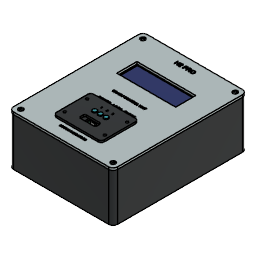
H2_Brain_LCD2004_v2 (Autodesk Fusion 360 design; units mm, degrees)
part number: 2026-09-27-10-19-20-342
part number: 2026-09-27-10-19-20-901
part number: 2026-09-27-10-19-24-013
part number: 2026-09-27-15-15-21-685
part number: 2026-09-27-15-15-23-118
part number: 2026-09-27-15-15-24-603
part number: 2026-09-27-15-15-26-161
part number: 2026-09-27-15-15-30-114
part number: 2026-09-27-15-15-31-956
part number: 2026-09-27-15-15-34-204
part number: 2026-09-27-15-15-36-656
part number: 2026-09-27-15-16-00-615
part number: 2026-09-27-15-16-12-198
part number: 2026-09-27-15-16-21-638
part number: 2026-09-27-15-16-25-058
part number: 2026-09-27-15-16-28-628
part number: 2026-09-27-15-16-32-419
part number: 2026-09-27-15-16-41-513
part number: 2026-09-27-15-16-51-300
part number: 2026-09-27-15-16-59-143
Autodesk Fusion 360 part; units mm, degrees
(part 1 of 2)
sketch "Outer shell sketch" plane through (0, 0, 0) normal (0, 0, 1) x (1, 0, 0) in component "01 BASE - PCB at bottom"
  line L0 (6, 0) -> (134, 0)
  line L1 (140, 6) -> (140, 154)
  line L2 (134, 160) -> (6, 160)
  line L3 (0, 154) -> (0, 6)
  arc A0 (134, 0) -> (140, 6) centre (134, 6) ccw
  arc A1 (140, 154) -> (134, 160) centre (134, 154) ccw
  arc A2 (6, 160) -> (0, 154) centre (6, 154) ccw
  arc A3 (0, 6) -> (6, 0) centre (6, 6) ccw
extrude "Outer shell" add sketch "Outer shell sketch" along normal blind 52 makes body 1 in component "01 BASE - PCB at bottom"
ref_plane "WorkPlane1" through (0, 0, 3) normal (0, 0, 1) x (1, 0, 0) in component "01 BASE - PCB at bottom"
sketch "Hollow cavity sketch" plane through (0, 0, 3) normal (0, 0, 1) x (1, 0, 0) in component "01 BASE - PCB at bottom"
  line L0 (6, 3) -> (134, 3)
  line L1 (137, 6) -> (137, 154)
  line L2 (134, 157) -> (6, 157)
  line L3 (3, 154) -> (3, 6)
  arc A0 (134, 3) -> (137, 6) centre (134, 6) ccw
  arc A1 (137, 154) -> (134, 157) centre (134, 154) ccw
  arc A2 (6, 157) -> (3, 154) centre (6, 154) ccw
  arc A3 (3, 6) -> (6, 3) centre (6, 6) ccw
extrude "Hollow cavity" cut sketch "Hollow cavity sketch" along normal blind 50 bodies 1 in component "01 BASE - PCB at bottom"
ref_plane "WorkPlane2" through (0, 0, 3) normal (0, 0, 1) x (1, 0, 0) in component "01 BASE - PCB at bottom"
sketch "Four lid screw pillars" plane through (0, 0, 3) normal (0, 0, 1) x (1, 0, 0) in component "01 BASE - PCB at bottom"
  line L0 (3, 3) -> (13, 3)
  line L1 (13, 3) -> (13, 13)
  line L2 (13, 13) -> (3, 13)
  line L3 (3, 13) -> (3, 3)
  line L4 (127, 3) -> (137, 3)
  line L5 (137, 3) -> (137, 13)
  line L6 (137, 13) -> (127, 13)
  line L7 (127, 13) -> (127, 3)
  line L8 (3, 147) -> (13, 147)
  line L9 (13, 147) -> (13, 157)
  line L10 (13, 157) -> (3, 157)
  line L11 (3, 157) -> (3, 147)
  line L12 (127, 147) -> (137, 147)
  line L13 (137, 147) -> (137, 157)
  line L14 (137, 157) -> (127, 157)
  line L15 (127, 157) -> (127, 147)
extrude "Lid pillars" add sketch "Four lid screw pillars" along normal blind 49 bodies 1 in component "01 BASE - PCB at bottom"
ref_plane "WorkPlane3" through (0, 0, 40) normal (0, 0, 1) x (1, 0, 0) in component "01 BASE - PCB at bottom"
sketch "M3 lid pilot holes sketch" plane through (0, 0, 40) normal (0, 0, 1) x (1, 0, 0) in component "01 BASE - PCB at bottom"
  circle A0 centre (8, 8) radius 1.25
  circle A1 centre (132, 8) radius 1.25
  circle A2 centre (8, 152) radius 1.25
  circle A3 centre (132, 152) radius 1.25
  dimension "d17" = 2.5
  dimension "d18" = 2.5
  dimension "d19" = 2.5
  dimension "d20" = 2.5
  measures "d17" diameter of A0
  measures "d18" diameter of A1
  measures "d19" diameter of A2
  measures "d20" diameter of A3
extrude "M3 lid pilot holes" cut sketch "M3 lid pilot holes sketch" along normal blind 12.1 bodies 1 in component "01 BASE - PCB at bottom"
ref_plane "WorkPlane4" through (0, 0, 3) normal (0, 0, 1) x (1, 0, 0) in component "01 BASE - PCB at bottom"
sketch "PCB support pads" plane through (0, 0, 3) normal (0, 0, 1) x (1, 0, 0) in component "01 BASE - PCB at bottom"
  line L0 (23, 40) -> (29, 40)
  line L1 (29, 40) -> (29, 50)
  line L2 (29, 50) -> (23, 50)
  line L3 (23, 50) -> (23, 40)
  line L4 (23, 110) -> (29, 110)
  line L5 (29, 110) -> (29, 120)
  line L6 (29, 120) -> (23, 120)
  line L7 (23, 120) -> (23, 110)
  line L8 (111, 40) -> (117, 40)
  line L9 (117, 40) -> (117, 50)
  line L10 (117, 50) -> (111, 50)
  line L11 (111, 50) -> (111, 40)
  line L12 (111, 110) -> (117, 110)
  line L13 (117, 110) -> (117, 120)
  line L14 (117, 120) -> (111, 120)
  line L15 (111, 120) -> (111, 110)
extrude "PCB supports z8" add sketch "PCB support pads" along normal blind 5 bodies 1 in component "01 BASE - PCB at bottom"
ref_plane "WorkPlane5" through (0, 0, 3) normal (0, 0, 1) x (1, 0, 0) in component "01 BASE - PCB at bottom"
sketch "PCB lateral guides" plane through (0, 0, 3) normal (0, 0, 1) x (1, 0, 0) in component "01 BASE - PCB at bottom"
  line L0 (22.2, 40) -> (24.6, 40)
  line L1 (24.6, 40) -> (24.6, 50)
  line L2 (24.6, 50) -> (22.2, 50)
  line L3 (22.2, 50) -> (22.2, 40)
  line L4 (22.2, 110) -> (24.6, 110)
  line L5 (24.6, 110) -> (24.6, 120)
  line L6 (24.6, 120) -> (22.2, 120)
  line L7 (22.2, 120) -> (22.2, 110)
  line L8 (115.4, 40) -> (117.8, 40)
  line L9 (117.8, 40) -> (117.8, 50)
  line L10 (117.8, 50) -> (115.4, 50)
  line L11 (115.4, 50) -> (115.4, 40)
  line L12 (115.4, 110) -> (117.8, 110)
  line L13 (117.8, 110) -> (117.8, 120)
  line L14 (117.8, 120) -> (115.4, 120)
  line L15 (115.4, 120) -> (115.4, 110)
  line L16 (55, 27.2) -> (85, 27.2)
  line L17 (85, 27.2) -> (85, 29.6)
  line L18 (85, 29.6) -> (55, 29.6)
  line L19 (55, 29.6) -> (55, 27.2)
  line L20 (55, 130.4) -> (85, 130.4)
  line L21 (85, 130.4) -> (85, 132.8)
  line L22 (85, 132.8) -> (55, 132.8)
  line L23 (55, 132.8) -> (55, 130.4)
extrude "Board edge guides clearance 0.4" add sketch "PCB lateral guides" along normal blind 6.6 bodies 1 in component "01 BASE - PCB at bottom"
ref_plane "WorkPlane6" through (0, 0, 3) normal (0, 0, 1) x (1, 0, 0) in component "01 BASE - PCB at bottom"
sketch "Clamp screw pedestals sketch" plane through (0, 0, 3) normal (0, 0, 1) x (1, 0, 0) in component "01 BASE - PCB at bottom"
  circle A0 centre (20, 45) radius 4
  circle A1 centre (120, 45) radius 4
  circle A2 centre (20, 115) radius 4
  circle A3 centre (120, 115) radius 4
extrude "Clamp screw pedestals" add sketch "Clamp screw pedestals sketch" along normal blind 6.6 bodies 1 in component "01 BASE - PCB at bottom"
ref_plane "WorkPlane7" through (0, 0, 3.1) normal (0, 0, 1) x (1, 0, 0) in component "01 BASE - PCB at bottom"
sketch "M3 clamp pilots sketch" plane through (0, 0, 3.1) normal (0, 0, 1) x (1, 0, 0) in component "01 BASE - PCB at bottom"
  circle A0 centre (20, 45) radius 1.25
  circle A1 centre (120, 45) radius 1.25
  circle A2 centre (20, 115) radius 1.25
  circle A3 centre (120, 115) radius 1.25
  dimension "d37" = 2.5
  dimension "d38" = 2.5
  dimension "d39" = 2.5
  dimension "d40" = 2.5
  measures "d37" diameter of A0
  measures "d38" diameter of A1
  measures "d39" diameter of A2
  measures "d40" diameter of A3
extrude "M3 clamp pilots" cut sketch "M3 clamp pilots sketch" along normal blind 6.6 bodies 1 in component "01 BASE - PCB at bottom"
ref_plane "WorkPlane1" through (0, 0, 52) normal (0, 0, 1) x (1, 0, 0) in component "02 LID - LCD buttons LEDs"
sketch "Lid plate sketch" plane through (0, 0, 52) normal (0, 0, 1) x (1, 0, 0) in component "02 LID - LCD buttons LEDs"
  line L0 (6, 0) -> (134, 0)
  line L1 (140, 6) -> (140, 154)
  line L2 (134, 160) -> (6, 160)
  line L3 (0, 154) -> (0, 6)
  arc A0 (134, 0) -> (140, 6) centre (134, 6) ccw
  arc A1 (140, 154) -> (134, 160) centre (134, 154) ccw
  arc A2 (6, 160) -> (0, 154) centre (6, 154) ccw
  arc A3 (0, 6) -> (6, 0) centre (6, 6) ccw
extrude "Lid plate" add sketch "Lid plate sketch" along normal blind 3 separate body makes body 2 in component "02 LID - LCD buttons LEDs"
ref_plane "WorkPlane2" through (0, 0, 48) normal (0, 0, 1) x (1, 0, 0) in component "02 LID - LCD buttons LEDs"
sketch "Locating lip segments - 0.3 clearance" plane through (0, 0, 48) normal (0, 0, 1) x (1, 0, 0) in component "02 LID - LCD buttons LEDs"
  line L0 (3.3, 16) -> (5.3, 16)
  line L1 (5.3, 16) -> (5.3, 144)
  line L2 (5.3, 144) -> (3.3, 144)
  line L3 (3.3, 144) -> (3.3, 16)
  line L4 (134.7, 16) -> (136.7, 16)
  line L5 (136.7, 16) -> (136.7, 144)
  line L6 (136.7, 144) -> (134.7, 144)
  line L7 (134.7, 144) -> (134.7, 16)
  line L8 (16, 3.3) -> (124, 3.3)
  line L9 (124, 3.3) -> (124, 5.3)
  line L10 (124, 5.3) -> (16, 5.3)
  line L11 (16, 5.3) -> (16, 3.3)
  line L12 (16, 154.7) -> (124, 154.7)
  line L13 (124, 154.7) -> (124, 156.7)
  line L14 (124, 156.7) -> (16, 156.7)
  line L15 (16, 156.7) -> (16, 154.7)
extrude "Locating lips" add sketch "Locating lip segments - 0.3 clearance" along normal blind 4 bodies 2 in component "02 LID - LCD buttons LEDs"
ref_plane "WorkPlane3" through (0, 0, 51.9) normal (0, 0, 1) x (1, 0, 0) in component "02 LID - LCD buttons LEDs"
sketch "M3 lid through holes sketch" plane through (0, 0, 51.9) normal (0, 0, 1) x (1, 0, 0) in component "02 LID - LCD buttons LEDs"
  circle A0 centre (8, 8) radius 1.7
  circle A1 centre (132, 8) radius 1.7
  circle A2 centre (8, 152) radius 1.7
  circle A3 centre (132, 152) radius 1.7
  dimension "d53" = 3.4
  dimension "d54" = 3.4
  dimension "d55" = 3.4
  dimension "d56" = 3.4
  measures "d53" diameter of A0
  measures "d54" diameter of A1
  measures "d55" diameter of A2
  measures "d56" diameter of A3
extrude "M3 lid through holes" cut sketch "M3 lid through holes sketch" along normal blind 3.2 bodies 2 in component "02 LID - LCD buttons LEDs"
ref_plane "WorkPlane4" through (0, 0, 53.8) normal (0, 0, 1) x (1, 0, 0) in component "02 LID - LCD buttons LEDs"
sketch "Screw head pockets sketch" plane through (0, 0, 53.8) normal (0, 0, 1) x (1, 0, 0) in component "02 LID - LCD buttons LEDs"
  circle A0 centre (8, 8) radius 3.2
  circle A1 centre (132, 8) radius 3.2
  circle A2 centre (8, 152) radius 3.2
  circle A3 centre (132, 152) radius 3.2
extrude "Screw head pockets" cut sketch "Screw head pockets sketch" along normal blind 1.3 bodies 2 in component "02 LID - LCD buttons LEDs"
ref_plane "WorkPlane5" through (0, 0, 51.9) normal (0, 0, 1) x (1, 0, 0) in component "02 LID - LCD buttons LEDs"
sketch "LCD viewing aperture sketch" plane through (0, 0, 51.9) normal (0, 0, 1) x (1, 0, 0) in component "02 LID - LCD buttons LEDs"
  line L0 (30.5, 99.5) -> (109.5, 99.5)
  line L1 (109.5, 99.5) -> (109.5, 126.5)
  line L2 (109.5, 126.5) -> (30.5, 126.5)
  line L3 (30.5, 126.5) -> (30.5, 99.5)
extrude "LCD viewing aperture" cut sketch "LCD viewing aperture sketch" along normal blind 3.2 bodies 2 in component "02 LID - LCD buttons LEDs"
ref_plane "WorkPlane6" through (0, 0, 42) normal (0, 0, 1) x (1, 0, 0) in component "02 LID - LCD buttons LEDs"
sketch "LCD underside spacers sketch" plane through (0, 0, 42) normal (0, 0, 1) x (1, 0, 0) in component "02 LID - LCD buttons LEDs"
  circle A0 centre (23.5, 85.5) radius 3.5
  circle A1 centre (116.5, 85.5) radius 3.5
  circle A2 centre (23.5, 140.5) radius 3.5
  circle A3 centre (116.5, 140.5) radius 3.5
extrude "LCD underside spacers" add sketch "LCD underside spacers sketch" along normal blind 10 bodies 2 in component "02 LID - LCD buttons LEDs"
ref_plane "WorkPlane7" through (0, 0, 41.9) normal (0, 0, 1) x (1, 0, 0) in component "02 LID - LCD buttons LEDs"
sketch "LCD M3 pilot holes sketch" plane through (0, 0, 41.9) normal (0, 0, 1) x (1, 0, 0) in component "02 LID - LCD buttons LEDs"
  circle A0 centre (23.5, 85.5) radius 1.25
  circle A1 centre (116.5, 85.5) radius 1.25
  circle A2 centre (23.5, 140.5) radius 1.25
  circle A3 centre (116.5, 140.5) radius 1.25
  dimension "d73" = 2.5
  dimension "d74" = 2.5
  dimension "d75" = 2.5
  dimension "d76" = 2.5
  measures "d73" diameter of A0
  measures "d74" diameter of A1
  measures "d75" diameter of A2
  measures "d76" diameter of A3
extrude "LCD M3 pilot holes" cut sketch "LCD M3 pilot holes sketch" along normal blind 8.1 bodies 2 in component "02 LID - LCD buttons LEDs"
ref_plane "WorkPlane8" through (0, 0, 51.9) normal (0, 0, 1) x (1, 0, 0) in component "02 LID - LCD buttons LEDs"
sketch "Three panel buttons sketch" plane through (0, 0, 51.9) normal (0, 0, 1) x (1, 0, 0) in component "02 LID - LCD buttons LEDs"
  circle A0 centre (36, 65) radius 6.1
  circle A1 centre (70, 65) radius 6.1
  circle A2 centre (104, 65) radius 6.1
  dimension "d81" = 12.2
  dimension "d82" = 12.2
  dimension "d83" = 12.2
  measures "d81" diameter of A0
  measures "d82" diameter of A1
  measures "d83" diameter of A2
extrude "Three panel buttons" cut sketch "Three panel buttons sketch" along normal blind 3.2 bodies 2 in component "02 LID - LCD buttons LEDs"
ref_plane "WorkPlane9" through (0, 0, 51.9) normal (0, 0, 1) x (1, 0, 0) in component "02 LID - LCD buttons LEDs"
sketch "Three indicator LEDs sketch" plane through (0, 0, 51.9) normal (0, 0, 1) x (1, 0, 0) in component "02 LID - LCD buttons LEDs"
  circle A0 centre (36, 26) radius 2.6
  circle A1 centre (70, 26) radius 2.6
  circle A2 centre (104, 26) radius 2.6
  dimension "d88" = 5.2
  dimension "d89" = 5.2
  dimension "d90" = 5.2
  measures "d88" diameter of A0
  measures "d89" diameter of A1
  measures "d90" diameter of A2
extrude "Three indicator LEDs" cut sketch "Three indicator LEDs sketch" along normal blind 3.2 bodies 2 in component "02 LID - LCD buttons LEDs"
ref_plane "WorkPlane10" through (0, 0, 55) normal (0, 0, 1) x (1, 0, 0) in component "02 LID - LCD buttons LEDs"
sketch "Engraving H2 PRO" plane through (0, 0, 55) normal (0, 0, 1) x (1, 0, 0) in component "02 LID - LCD buttons LEDs"
  line L0 (37.5, 144.5) -> (102.5, 144.5) construction
  line L1 (102.5, 144.5) -> (102.5, 149.5) construction
  line L2 (102.5, 149.5) -> (37.5, 149.5) construction
  line L3 (37.5, 149.5) -> (37.5, 144.5) construction
  dimension "d95" = 4
  dimension "d96" = 0
  text T0 "H2 PRO" font "Arial" height 4 align centre middle in box 65 x 5 at (37.5, 144.5) x (1, 0) y (0, 1) spacing 1 kerned
extrude "Engrave H2 PRO" cut sketch "Engraving H2 PRO" against normal blind 0.4 text T0 bodies 2 in component "02 LID - LCD buttons LEDs"
ref_plane "WorkPlane11" through (0, 0, 55) normal (0, 0, 1) x (1, 0, 0) in component "02 LID - LCD buttons LEDs"
sketch "Engraving POWER" plane through (0, 0, 55) normal (0, 0, 1) x (1, 0, 0) in component "02 LID - LCD buttons LEDs"
  line L0 (21, 48.5) -> (51, 48.5) construction
  line L1 (51, 48.5) -> (51, 53.5) construction
  line L2 (51, 53.5) -> (21, 53.5) construction
  line L3 (21, 53.5) -> (21, 48.5) construction
  dimension "d101" = 3
  text T0 "POWER" font "Arial" height 3 align centre middle in box 30 x 5 at (21, 48.5) x (1, 0) y (0, 1) spacing 1 kerned
extrude "Engrave POWER" cut sketch "Engraving POWER" against normal blind 0.4 text T0 bodies 2 in component "02 LID - LCD buttons LEDs"
ref_plane "WorkPlane12" through (0, 0, 55) normal (0, 0, 1) x (1, 0, 0) in component "02 LID - LCD buttons LEDs"
sketch "Engraving LOCK" plane through (0, 0, 55) normal (0, 0, 1) x (1, 0, 0) in component "02 LID - LCD buttons LEDs"
  line L0 (55, 48.5) -> (85, 48.5) construction
  line L1 (85, 48.5) -> (85, 53.5) construction
  line L2 (85, 53.5) -> (55, 53.5) construction
  line L3 (55, 53.5) -> (55, 48.5) construction
  dimension "d107" = 3
  text T0 "LOCK" font "Arial" height 3 align centre middle in box 30 x 5 at (55, 48.5) x (1, 0) y (0, 1) spacing 1 kerned
extrude "Engrave LOCK" cut sketch "Engraving LOCK" against normal blind 0.4 text T0 bodies 2 in component "02 LID - LCD buttons LEDs"
ref_plane "WorkPlane13" through (0, 0, 55) normal (0, 0, 1) x (1, 0, 0) in component "02 LID - LCD buttons LEDs"
sketch "Engraving PURGE" plane through (0, 0, 55) normal (0, 0, 1) x (1, 0, 0) in component "02 LID - LCD buttons LEDs"
  line L0 (89, 48.5) -> (119, 48.5) construction
  line L1 (119, 48.5) -> (119, 53.5) construction
  line L2 (119, 53.5) -> (89, 53.5) construction
  line L3 (89, 53.5) -> (89, 48.5) construction
  dimension "d113" = 3
  text T0 "PURGE" font "Arial" height 3 align centre middle in box 30 x 5 at (89, 48.5) x (1, 0) y (0, 1) spacing 1 kerned
extrude "Engrave PURGE" cut sketch "Engraving PURGE" against normal blind 0.4 text T0 bodies 2 in component "02 LID - LCD buttons LEDs"
ref_plane "WorkPlane14" through (0, 0, 55) normal (0, 0, 1) x (1, 0, 0) in component "02 LID - LCD buttons LEDs"
sketch "Engraving POWER (1)" plane through (0, 0, 55) normal (0, 0, 1) x (1, 0, 0) in component "02 LID - LCD buttons LEDs"
  line L0 (21, 13.5) -> (51, 13.5) construction
  line L1 (51, 13.5) -> (51, 18.5) construction
  line L2 (51, 18.5) -> (21, 18.5) construction
  line L3 (21, 18.5) -> (21, 13.5) construction
  dimension "d119" = 2.5
  text T0 "POWER" font "Arial" height 2.5 align centre middle in box 30 x 5 at (21, 13.5) x (1, 0) y (0, 1) spacing 1 kerned
extrude "Engrave POWER (1)" cut sketch "Engraving POWER (1)" against normal blind 0.4 text T0 bodies 2 in component "02 LID - LCD buttons LEDs"
ref_plane "WorkPlane15" through (0, 0, 55) normal (0, 0, 1) x (1, 0, 0) in component "02 LID - LCD buttons LEDs"
sketch "Engraving LOCK (1)" plane through (0, 0, 55) normal (0, 0, 1) x (1, 0, 0) in component "02 LID - LCD buttons LEDs"
  line L0 (55, 13.5) -> (85, 13.5) construction
  line L1 (85, 13.5) -> (85, 18.5) construction
  line L2 (85, 18.5) -> (55, 18.5) construction
  line L3 (55, 18.5) -> (55, 13.5) construction
  dimension "d125" = 2.5
  text T0 "LOCK" font "Arial" height 2.5 align centre middle in box 30 x 5 at (55, 13.5) x (1, 0) y (0, 1) spacing 1 kerned
extrude "Engrave LOCK (1)" cut sketch "Engraving LOCK (1)" against normal blind 0.4 text T0 bodies 2 in component "02 LID - LCD buttons LEDs"
ref_plane "WorkPlane16" through (0, 0, 55) normal (0, 0, 1) x (1, 0, 0) in component "02 LID - LCD buttons LEDs"
sketch "Engraving MODE" plane through (0, 0, 55) normal (0, 0, 1) x (1, 0, 0) in component "02 LID - LCD buttons LEDs"
  line L0 (89, 13.5) -> (119, 13.5) construction
  line L1 (119, 13.5) -> (119, 18.5) construction
  line L2 (119, 18.5) -> (89, 18.5) construction
  line L3 (89, 18.5) -> (89, 13.5) construction
  dimension "d131" = 2.5
  text T0 "MODE" font "Arial" height 2.5 align centre middle in box 30 x 5 at (89, 13.5) x (1, 0) y (0, 1) spacing 1 kerned
extrude "Engrave MODE" cut sketch "Engraving MODE" against normal blind 0.4 text T0 bodies 2 in component "02 LID - LCD buttons LEDs"
sketch "V2 extend existing base for relay bay sketch" plane through (0, 0, 0) normal (0, 0, 1) x (1, 0, 0) in component "01 BASE - PCB at bottom"
  line L0 (6, 0) -> (134, 0)
  line L1 (140, 6) -> (140, 174)
  line L2 (134, 180) -> (6, 180)
  line L3 (0, 174) -> (0, 6)
  arc A0 (134, 0) -> (140, 6) centre (134, 6) ccw
  arc A1 (140, 174) -> (134, 180) centre (134, 174) ccw
  arc A2 (6, 180) -> (0, 174) centre (6, 174) ccw
  arc A3 (0, 6) -> (6, 0) centre (6, 6) ccw
extrude "V2 extend existing base for relay bay" add sketch "V2 extend existing base for relay bay sketch" along normal blind 64 bodies 1 in component "01 BASE - PCB at bottom"
ref_plane "WorkPlane8" through (0, 0, 3) normal (0, 0, 1) x (1, 0, 0) in component "01 BASE - PCB at bottom"
sketch "V2 clear obsolete interior mounts sketch" plane through (0, 0, 3) normal (0, 0, 1) x (1, 0, 0) in component "01 BASE - PCB at bottom"
  line L0 (6, 3) -> (134, 3)
  line L1 (137, 6) -> (137, 174)
  line L2 (134, 177) -> (6, 177)
  line L3 (3, 174) -> (3, 6)
  arc A0 (134, 3) -> (137, 6) centre (134, 6) ccw
  arc A1 (137, 174) -> (134, 177) centre (134, 174) ccw
  arc A2 (6, 177) -> (3, 174) centre (6, 174) ccw
  arc A3 (3, 6) -> (6, 3) centre (6, 6) ccw
extrude "V2 clear obsolete interior mounts" cut sketch "V2 clear obsolete interior mounts sketch" along normal blind 62 bodies 1 in component "01 BASE - PCB at bottom"
ref_plane "WorkPlane9" through (0, 0, 3) normal (0, 0, 1) x (1, 0, 0) in component "01 BASE - PCB at bottom"
sketch "V2 lid pillars" plane through (0, 0, 3) normal (0, 0, 1) x (1, 0, 0) in component "01 BASE - PCB at bottom"
  line L0 (3, 3) -> (13, 3)
  line L1 (13, 3) -> (13, 13)
  line L2 (13, 13) -> (3, 13)
  line L3 (3, 13) -> (3, 3)
  line L4 (127, 3) -> (137, 3)
  line L5 (137, 3) -> (137, 13)
  line L6 (137, 13) -> (127, 13)
  line L7 (127, 13) -> (127, 3)
  line L8 (3, 167) -> (13, 167)
  line L9 (13, 167) -> (13, 177)
  line L10 (13, 177) -> (3, 177)
  line L11 (3, 177) -> (3, 167)
  line L12 (127, 167) -> (137, 167)
  line L13 (137, 167) -> (137, 177)
  line L14 (137, 177) -> (127, 177)
  line L15 (127, 177) -> (127, 167)
extrude "V2 four cover pillars" add sketch "V2 lid pillars" along normal blind 61 bodies 1 in component "01 BASE - PCB at bottom"
ref_plane "WorkPlane10" through (0, 0, 52) normal (0, 0, 1) x (1, 0, 0) in component "01 BASE - PCB at bottom"
sketch "V2 lid pilots sketch" plane through (0, 0, 52) normal (0, 0, 1) x (1, 0, 0) in component "01 BASE - PCB at bottom"
  circle A0 centre (8, 8) radius 1.25
  circle A1 centre (132, 8) radius 1.25
  circle A2 centre (8, 172) radius 1.25
  circle A3 centre (132, 172) radius 1.25
extrude "V2 lid pilots" cut sketch "V2 lid pilots sketch" along normal blind 12.2 bodies 1 in component "01 BASE - PCB at bottom"
ref_plane "WorkPlane11" through (0, 0, 3) normal (0, 0, 1) x (1, 0, 0) in component "01 BASE - PCB at bottom"
sketch "V2 MAIN supports" plane through (0, 0, 3) normal (0, 0, 1) x (1, 0, 0) in component "01 BASE - PCB at bottom"
  line L0 (23, 30) -> (29, 30)
  line L1 (29, 30) -> (29, 40)
  line L2 (29, 40) -> (23, 40)
  line L3 (23, 40) -> (23, 30)
  line L4 (23, 80) -> (29, 80)
  line L5 (29, 80) -> (29, 90)
  line L6 (29, 90) -> (23, 90)
  line L7 (23, 90) -> (23, 80)
  line L8 (111, 30) -> (117, 30)
  line L9 (117, 30) -> (117, 40)
  line L10 (117, 40) -> (111, 40)
  line L11 (111, 40) -> (111, 30)
  line L12 (111, 80) -> (117, 80)
  line L13 (117, 80) -> (117, 90)
  line L14 (117, 90) -> (111, 90)
  line L15 (111, 90) -> (111, 80)
extrude "V2 MAIN underside edge pads" add sketch "V2 MAIN supports" along normal blind 5 bodies 1 in component "01 BASE - PCB at bottom"
ref_plane "WorkPlane12" through (0, 0, 3) normal (0, 0, 1) x (1, 0, 0) in component "01 BASE - PCB at bottom"
sketch "V2 MAIN clamp pedestals sketch" plane through (0, 0, 3) normal (0, 0, 1) x (1, 0, 0) in component "01 BASE - PCB at bottom"
  circle A0 centre (20, 35) radius 4
  circle A1 centre (120, 35) radius 4
  circle A2 centre (20, 85) radius 4
  circle A3 centre (120, 85) radius 4
extrude "V2 MAIN clamp pedestals" add sketch "V2 MAIN clamp pedestals sketch" along normal blind 6.6 bodies 1 in component "01 BASE - PCB at bottom"
ref_plane "WorkPlane13" through (0, 0, 3.1) normal (0, 0, 1) x (1, 0, 0) in component "01 BASE - PCB at bottom"
sketch "V2 MAIN clamp pilots sketch" plane through (0, 0, 3.1) normal (0, 0, 1) x (1, 0, 0) in component "01 BASE - PCB at bottom"
  circle A0 centre (20, 35) radius 1.25
  circle A1 centre (120, 35) radius 1.25
  circle A2 centre (20, 85) radius 1.25
  circle A3 centre (120, 85) radius 1.25
extrude "V2 MAIN clamp pilots" cut sketch "V2 MAIN clamp pilots sketch" along normal blind 6.6 bodies 1 in component "01 BASE - PCB at bottom"
ref_plane "WorkPlane1" through (0, 0, 9.6) normal (0, 0, 1) x (1, 0, 0) in component "V2 MAIN clamp 1"
sketch "Edge clamp sketch" plane through (0, 0, 9.6) normal (0, 0, 1) x (1, 0, 0) in component "V2 MAIN clamp 1"
  line L0 (17, 30) -> (27.5, 30)
  line L1 (28.5, 31) -> (28.5, 39)
  line L2 (27.5, 40) -> (17, 40)
  line L3 (16, 39) -> (16, 31)
  arc A0 (27.5, 30) -> (28.5, 31) centre (27.5, 31) ccw
  arc A1 (28.5, 39) -> (27.5, 40) centre (27.5, 39) ccw
  arc A2 (17, 40) -> (16, 39) centre (17, 39) ccw
  arc A3 (16, 31) -> (17, 30) centre (17, 31) ccw
extrude "Edge clamp" add sketch "Edge clamp sketch" along normal blind 2.5 separate body makes body 3 in component "V2 MAIN clamp 1"
ref_plane "WorkPlane2" through (0, 0, 9.5) normal (0, 0, 1) x (1, 0, 0) in component "V2 MAIN clamp 1"
sketch "Clamp adjustment slot" plane through (0, 0, 9.5) normal (0, 0, 1) x (1, 0, 0) in component "V2 MAIN clamp 1"
  line L0 (18.4, 33.3) -> (21.6, 33.3)
  line L1 (23.2, 34.9) -> (23.2, 35.1)
  line L2 (21.6, 36.7) -> (18.4, 36.7)
  line L3 (16.8, 35.1) -> (16.8, 34.9)
  arc A0 (21.6, 33.3) -> (23.2, 34.9) centre (21.6, 34.9) ccw
  arc A1 (23.2, 35.1) -> (21.6, 36.7) centre (21.6, 35.1) ccw
  arc A2 (18.4, 36.7) -> (16.8, 35.1) centre (18.4, 35.1) ccw
  arc A3 (16.8, 34.9) -> (18.4, 33.3) centre (18.4, 34.9) ccw
extrude "Clamp adjustment slot (1)" cut sketch "Clamp adjustment slot" along normal blind 2.8 bodies 3 in component "V2 MAIN clamp 1"
ref_plane "WorkPlane1" through (0, 0, 9.6) normal (0, 0, 1) x (1, 0, 0) in component "V2 MAIN clamp 2"
sketch "Edge clamp sketch (2)" plane through (0, 0, 9.6) normal (0, 0, 1) x (1, 0, 0) in component "V2 MAIN clamp 2"
  line L0 (112.5, 30) -> (123, 30)
  line L1 (124, 31) -> (124, 39)
  line L2 (123, 40) -> (112.5, 40)
  line L3 (111.5, 39) -> (111.5, 31)
  arc A0 (123, 30) -> (124, 31) centre (123, 31) ccw
  arc A1 (124, 39) -> (123, 40) centre (123, 39) ccw
  arc A2 (112.5, 40) -> (111.5, 39) centre (112.5, 39) ccw
  arc A3 (111.5, 31) -> (112.5, 30) centre (112.5, 31) ccw
extrude "Edge clamp'" add sketch "Edge clamp sketch (2)" along normal blind 2.5 separate body makes body 4 in component "V2 MAIN clamp 2"
ref_plane "WorkPlane2" through (0, 0, 9.5) normal (0, 0, 1) x (1, 0, 0) in component "V2 MAIN clamp 2"
sketch "Clamp adjustment slot (2)" plane through (0, 0, 9.5) normal (0, 0, 1) x (1, 0, 0) in component "V2 MAIN clamp 2"
  line L0 (118.4, 33.3) -> (121.6, 33.3)
  line L1 (123.2, 34.9) -> (123.2, 35.1)
  line L2 (121.6, 36.7) -> (118.4, 36.7)
  line L3 (116.8, 35.1) -> (116.8, 34.9)
  arc A0 (121.6, 33.3) -> (123.2, 34.9) centre (121.6, 34.9) ccw
  arc A1 (123.2, 35.1) -> (121.6, 36.7) centre (121.6, 35.1) ccw
  arc A2 (118.4, 36.7) -> (116.8, 35.1) centre (118.4, 35.1) ccw
  arc A3 (116.8, 34.9) -> (118.4, 33.3) centre (118.4, 34.9) ccw
extrude "Clamp adjustment slot (1)'" cut sketch "Clamp adjustment slot (2)" along normal blind 2.8 bodies 4 in component "V2 MAIN clamp 2"
ref_plane "WorkPlane1" through (0, 0, 9.6) normal (0, 0, 1) x (1, 0, 0) in component "V2 MAIN clamp 3"
sketch "Edge clamp sketch (3)" plane through (0, 0, 9.6) normal (0, 0, 1) x (1, 0, 0) in component "V2 MAIN clamp 3"
  line L0 (17, 80) -> (27.5, 80)
  line L1 (28.5, 81) -> (28.5, 89)
  line L2 (27.5, 90) -> (17, 90)
  line L3 (16, 89) -> (16, 81)
  arc A0 (27.5, 80) -> (28.5, 81) centre (27.5, 81) ccw
  arc A1 (28.5, 89) -> (27.5, 90) centre (27.5, 89) ccw
  arc A2 (17, 90) -> (16, 89) centre (17, 89) ccw
  arc A3 (16, 81) -> (17, 80) centre (17, 81) ccw
extrude "Edge clamp''" add sketch "Edge clamp sketch (3)" along normal blind 2.5 separate body makes body 5 in component "V2 MAIN clamp 3"
ref_plane "WorkPlane2" through (0, 0, 9.5) normal (0, 0, 1) x (1, 0, 0) in component "V2 MAIN clamp 3"
sketch "Clamp adjustment slot (3)" plane through (0, 0, 9.5) normal (0, 0, 1) x (1, 0, 0) in component "V2 MAIN clamp 3"
  line L0 (18.4, 83.3) -> (21.6, 83.3)
  line L1 (23.2, 84.9) -> (23.2, 85.1)
  line L2 (21.6, 86.7) -> (18.4, 86.7)
  line L3 (16.8, 85.1) -> (16.8, 84.9)
  arc A0 (21.6, 83.3) -> (23.2, 84.9) centre (21.6, 84.9) ccw
  arc A1 (23.2, 85.1) -> (21.6, 86.7) centre (21.6, 85.1) ccw
  arc A2 (18.4, 86.7) -> (16.8, 85.1) centre (18.4, 85.1) ccw
  arc A3 (16.8, 84.9) -> (18.4, 83.3) centre (18.4, 84.9) ccw
extrude "Clamp adjustment slot (1)''" cut sketch "Clamp adjustment slot (3)" along normal blind 2.8 bodies 5 in component "V2 MAIN clamp 3"
ref_plane "WorkPlane1" through (0, 0, 9.6) normal (0, 0, 1) x (1, 0, 0) in component "V2 MAIN clamp 4"
sketch "Edge clamp sketch (4)" plane through (0, 0, 9.6) normal (0, 0, 1) x (1, 0, 0) in component "V2 MAIN clamp 4"
  line L0 (112.5, 80) -> (123, 80)
  line L1 (124, 81) -> (124, 89)
  line L2 (123, 90) -> (112.5, 90)
  line L3 (111.5, 89) -> (111.5, 81)
  arc A0 (123, 80) -> (124, 81) centre (123, 81) ccw
  arc A1 (124, 89) -> (123, 90) centre (123, 89) ccw
  arc A2 (112.5, 90) -> (111.5, 89) centre (112.5, 89) ccw
  arc A3 (111.5, 81) -> (112.5, 80) centre (112.5, 81) ccw
extrude "Edge clamp'''" add sketch "Edge clamp sketch (4)" along normal blind 2.5 separate body makes body 6 in component "V2 MAIN clamp 4"
ref_plane "WorkPlane2" through (0, 0, 9.5) normal (0, 0, 1) x (1, 0, 0) in component "V2 MAIN clamp 4"
sketch "Clamp adjustment slot (4)" plane through (0, 0, 9.5) normal (0, 0, 1) x (1, 0, 0) in component "V2 MAIN clamp 4"
  line L0 (118.4, 83.3) -> (121.6, 83.3)
  line L1 (123.2, 84.9) -> (123.2, 85.1)
  line L2 (121.6, 86.7) -> (118.4, 86.7)
  line L3 (116.8, 85.1) -> (116.8, 84.9)
  arc A0 (121.6, 83.3) -> (123.2, 84.9) centre (121.6, 84.9) ccw
  arc A1 (123.2, 85.1) -> (121.6, 86.7) centre (121.6, 85.1) ccw
  arc A2 (118.4, 86.7) -> (116.8, 85.1) centre (118.4, 85.1) ccw
  arc A3 (116.8, 84.9) -> (118.4, 83.3) centre (118.4, 84.9) ccw
extrude "Clamp adjustment slot (1)'''" cut sketch "Clamp adjustment slot (4)" along normal blind 2.8 bodies 6 in component "V2 MAIN clamp 4"
ref_plane "WorkPlane14" through (0, 0, 3) normal (0, 0, 1) x (1, 0, 0) in component "01 BASE - PCB at bottom"
sketch "V2 RELAY supports" plane through (0, 0, 3) normal (0, 0, 1) x (1, 0, 0) in component "01 BASE - PCB at bottom"
  line L0 (33, 122) -> (39, 122)
  line L1 (39, 122) -> (39, 132)
  line L2 (39, 132) -> (33, 132)
  line L3 (33, 132) -> (33, 122)
  line L4 (33, 152) -> (39, 152)
  line L5 (39, 152) -> (39, 162)
  line L6 (39, 162) -> (33, 162)
  line L7 (33, 162) -> (33, 152)
  line L8 (101, 122) -> (107, 122)
  line L9 (107, 122) -> (107, 132)
  line L10 (107, 132) -> (101, 132)
  line L11 (101, 132) -> (101, 122)
  line L12 (101, 152) -> (107, 152)
  line L13 (107, 152) -> (107, 162)
  line L14 (107, 162) -> (101, 162)
  line L15 (101, 162) -> (101, 152)
extrude "V2 RELAY underside edge pads" add sketch "V2 RELAY supports" along normal blind 5 bodies 1 in component "01 BASE - PCB at bottom"
ref_plane "WorkPlane15" through (0, 0, 3) normal (0, 0, 1) x (1, 0, 0) in component "01 BASE - PCB at bottom"
sketch "V2 RELAY clamp pedestals sketch" plane through (0, 0, 3) normal (0, 0, 1) x (1, 0, 0) in component "01 BASE - PCB at bottom"
  circle A0 centre (30, 127) radius 4
  circle A1 centre (110, 127) radius 4
  circle A2 centre (30, 157) radius 4
  circle A3 centre (110, 157) radius 4
extrude "V2 RELAY clamp pedestals" add sketch "V2 RELAY clamp pedestals sketch" along normal blind 6.6 bodies 1 in component "01 BASE - PCB at bottom"
ref_plane "WorkPlane16" through (0, 0, 3.1) normal (0, 0, 1) x (1, 0, 0) in component "01 BASE - PCB at bottom"
sketch "V2 RELAY clamp pilots sketch" plane through (0, 0, 3.1) normal (0, 0, 1) x (1, 0, 0) in component "01 BASE - PCB at bottom"
  circle A0 centre (30, 127) radius 1.25
  circle A1 centre (110, 127) radius 1.25
  circle A2 centre (30, 157) radius 1.25
  circle A3 centre (110, 157) radius 1.25
extrude "V2 RELAY clamp pilots" cut sketch "V2 RELAY clamp pilots sketch" along normal blind 6.6 bodies 1 in component "01 BASE - PCB at bottom"
ref_plane "WorkPlane1" through (0, 0, 9.6) normal (0, 0, 1) x (1, 0, 0) in component "V2 RELAY clamp 1"
sketch "Edge clamp sketch (5)" plane through (0, 0, 9.6) normal (0, 0, 1) x (1, 0, 0) in component "V2 RELAY clamp 1"
  line L0 (27, 122) -> (37.5, 122)
  line L1 (38.5, 123) -> (38.5, 131)
  line L2 (37.5, 132) -> (27, 132)
  line L3 (26, 131) -> (26, 123)
  arc A0 (37.5, 122) -> (38.5, 123) centre (37.5, 123) ccw
  arc A1 (38.5, 131) -> (37.5, 132) centre (37.5, 131) ccw
  arc A2 (27, 132) -> (26, 131) centre (27, 131) ccw
  arc A3 (26, 123) -> (27, 122) centre (27, 123) ccw
extrude "Edge clamp''''" add sketch "Edge clamp sketch (5)" along normal blind 2.5 separate body makes body 7 in component "V2 RELAY clamp 1"
ref_plane "WorkPlane2" through (0, 0, 9.5) normal (0, 0, 1) x (1, 0, 0) in component "V2 RELAY clamp 1"
sketch "Clamp adjustment slot (5)" plane through (0, 0, 9.5) normal (0, 0, 1) x (1, 0, 0) in component "V2 RELAY clamp 1"
  line L0 (28.4, 125.3) -> (31.6, 125.3)
  line L1 (33.2, 126.9) -> (33.2, 127.1)
  line L2 (31.6, 128.7) -> (28.4, 128.7)
  line L3 (26.8, 127.1) -> (26.8, 126.9)
  arc A0 (31.6, 125.3) -> (33.2, 126.9) centre (31.6, 126.9) ccw
  arc A1 (33.2, 127.1) -> (31.6, 128.7) centre (31.6, 127.1) ccw
  arc A2 (28.4, 128.7) -> (26.8, 127.1) centre (28.4, 127.1) ccw
  arc A3 (26.8, 126.9) -> (28.4, 125.3) centre (28.4, 126.9) ccw
extrude "Clamp adjustment slot (1)''''" cut sketch "Clamp adjustment slot (5)" along normal blind 2.8 bodies 7 in component "V2 RELAY clamp 1"
ref_plane "WorkPlane1" through (0, 0, 9.6) normal (0, 0, 1) x (1, 0, 0) in component "V2 RELAY clamp 2"
sketch "Edge clamp sketch (6)" plane through (0, 0, 9.6) normal (0, 0, 1) x (1, 0, 0) in component "V2 RELAY clamp 2"
  line L0 (102.5, 122) -> (113, 122)
  line L1 (114, 123) -> (114, 131)
  line L2 (113, 132) -> (102.5, 132)
  line L3 (101.5, 131) -> (101.5, 123)
  arc A0 (113, 122) -> (114, 123) centre (113, 123) ccw
  arc A1 (114, 131) -> (113, 132) centre (113, 131) ccw
  arc A2 (102.5, 132) -> (101.5, 131) centre (102.5, 131) ccw
  arc A3 (101.5, 123) -> (102.5, 122) centre (102.5, 123) ccw
extrude "Edge clamp'''''" add sketch "Edge clamp sketch (6)" along normal blind 2.5 separate body makes body 8 in component "V2 RELAY clamp 2"
ref_plane "WorkPlane2" through (0, 0, 9.5) normal (0, 0, 1) x (1, 0, 0) in component "V2 RELAY clamp 2"
sketch "Clamp adjustment slot (6)" plane through (0, 0, 9.5) normal (0, 0, 1) x (1, 0, 0) in component "V2 RELAY clamp 2"
  line L0 (108.4, 125.3) -> (111.6, 125.3)
  line L1 (113.2, 126.9) -> (113.2, 127.1)
  line L2 (111.6, 128.7) -> (108.4, 128.7)
  line L3 (106.8, 127.1) -> (106.8, 126.9)
  arc A0 (111.6, 125.3) -> (113.2, 126.9) centre (111.6, 126.9) ccw
  arc A1 (113.2, 127.1) -> (111.6, 128.7) centre (111.6, 127.1) ccw
  arc A2 (108.4, 128.7) -> (106.8, 127.1) centre (108.4, 127.1) ccw
  arc A3 (106.8, 126.9) -> (108.4, 125.3) centre (108.4, 126.9) ccw
extrude "Clamp adjustment slot (1)'''''" cut sketch "Clamp adjustment slot (6)" along normal blind 2.8 bodies 8 in component "V2 RELAY clamp 2"
ref_plane "WorkPlane1" through (0, 0, 9.6) normal (0, 0, 1) x (1, 0, 0) in component "V2 RELAY clamp 3"
sketch "Edge clamp sketch (7)" plane through (0, 0, 9.6) normal (0, 0, 1) x (1, 0, 0) in component "V2 RELAY clamp 3"
  line L0 (27, 152) -> (37.5, 152)
  line L1 (38.5, 153) -> (38.5, 161)
  line L2 (37.5, 162) -> (27, 162)
  line L3 (26, 161) -> (26, 153)
  arc A0 (37.5, 152) -> (38.5, 153) centre (37.5, 153) ccw
  arc A1 (38.5, 161) -> (37.5, 162) centre (37.5, 161) ccw
  arc A2 (27, 162) -> (26, 161) centre (27, 161) ccw
  arc A3 (26, 153) -> (27, 152) centre (27, 153) ccw
extrude "Edge clamp''''''" add sketch "Edge clamp sketch (7)" along normal blind 2.5 separate body makes body 9 in component "V2 RELAY clamp 3"
ref_plane "WorkPlane2" through (0, 0, 9.5) normal (0, 0, 1) x (1, 0, 0) in component "V2 RELAY clamp 3"
sketch "Clamp adjustment slot (7)" plane through (0, 0, 9.5) normal (0, 0, 1) x (1, 0, 0) in component "V2 RELAY clamp 3"
  line L0 (28.4, 155.3) -> (31.6, 155.3)
  line L1 (33.2, 156.9) -> (33.2, 157.1)
  line L2 (31.6, 158.7) -> (28.4, 158.7)
  line L3 (26.8, 157.1) -> (26.8, 156.9)
  arc A0 (31.6, 155.3) -> (33.2, 156.9) centre (31.6, 156.9) ccw
  arc A1 (33.2, 157.1) -> (31.6, 158.7) centre (31.6, 157.1) ccw
  arc A2 (28.4, 158.7) -> (26.8, 157.1) centre (28.4, 157.1) ccw
  arc A3 (26.8, 156.9) -> (28.4, 155.3) centre (28.4, 156.9) ccw
extrude "Clamp adjustment slot (1)''''''" cut sketch "Clamp adjustment slot (7)" along normal blind 2.8 bodies 9 in component "V2 RELAY clamp 3"
ref_plane "WorkPlane1" through (0, 0, 9.6) normal (0, 0, 1) x (1, 0, 0) in component "V2 RELAY clamp 4"
sketch "Edge clamp sketch (8)" plane through (0, 0, 9.6) normal (0, 0, 1) x (1, 0, 0) in component "V2 RELAY clamp 4"
  line L0 (102.5, 152) -> (113, 152)
  line L1 (114, 153) -> (114, 161)
  line L2 (113, 162) -> (102.5, 162)
  line L3 (101.5, 161) -> (101.5, 153)
  arc A0 (113, 152) -> (114, 153) centre (113, 153) ccw
  arc A1 (114, 161) -> (113, 162) centre (113, 161) ccw
  arc A2 (102.5, 162) -> (101.5, 161) centre (102.5, 161) ccw
  arc A3 (101.5, 153) -> (102.5, 152) centre (102.5, 153) ccw
extrude "Edge clamp'''''''" add sketch "Edge clamp sketch (8)" along normal blind 2.5 separate body makes body 10 in component "V2 RELAY clamp 4"
ref_plane "WorkPlane2" through (0, 0, 9.5) normal (0, 0, 1) x (1, 0, 0) in component "V2 RELAY clamp 4"
sketch "Clamp adjustment slot (8)" plane through (0, 0, 9.5) normal (0, 0, 1) x (1, 0, 0) in component "V2 RELAY clamp 4"
  line L0 (108.4, 155.3) -> (111.6, 155.3)
  line L1 (113.2, 156.9) -> (113.2, 157.1)
  line L2 (111.6, 158.7) -> (108.4, 158.7)
  line L3 (106.8, 157.1) -> (106.8, 156.9)
  arc A0 (111.6, 155.3) -> (113.2, 156.9) centre (111.6, 156.9) ccw
  arc A1 (113.2, 157.1) -> (111.6, 158.7) centre (111.6, 157.1) ccw
  arc A2 (108.4, 158.7) -> (106.8, 157.1) centre (108.4, 157.1) ccw
  arc A3 (106.8, 156.9) -> (108.4, 155.3) centre (108.4, 156.9) ccw
extrude "Clamp adjustment slot (1)'''''''" cut sketch "Clamp adjustment slot (8)" along normal blind 2.8 bodies 10 in component "V2 RELAY clamp 4"
ref_plane "WorkPlane17" through (0, -176.5, 0) normal (0, 1, 0) x (0, 0, 1) in component "01 BASE - PCB at bottom"
sketch "V2 rear wiring outlet" plane through (0, -176.5, 0) normal (0, 1, 0) x (1, 0, 0) in component "01 BASE - PCB at bottom"
  line L0 (40, 14) -> (60, 14)
  line L1 (62, 16) -> (62, 22)
  line L2 (60, 24) -> (40, 24)
  line L3 (38, 22) -> (38, 16)
  arc A0 (60, 14) -> (62, 16) centre (60, 16) ccw
  arc A1 (62, 22) -> (60, 24) centre (60, 22) ccw
  arc A2 (40, 24) -> (38, 22) centre (40, 22) ccw
  arc A3 (38, 16) -> (40, 14) centre (40, 16) ccw
ref_plane "WorkPlane18" through (0, -176.5, 0) normal (0, 1, 0) x (0, 0, 1) in component "01 BASE - PCB at bottom"
sketch "V2 rear wiring outlet (1)" plane through (0, -176.5, 0) normal (0, 1, 0) x (1, 0, 0) in component "01 BASE - PCB at bottom"
  line L0 (80, 14) -> (100, 14)
  line L1 (102, 16) -> (102, 22)
  line L2 (100, 24) -> (80, 24)
  line L3 (78, 22) -> (78, 16)
  arc A0 (100, 14) -> (102, 16) centre (100, 16) ccw
  arc A1 (102, 22) -> (100, 24) centre (100, 22) ccw
  arc A2 (80, 24) -> (78, 22) centre (80, 22) ccw
  arc A3 (78, 16) -> (80, 14) centre (80, 16) ccw
ref_plane "WorkPlane19" through (0, 0, 3) normal (0, 0, 1) x (1, 0, 0) in component "01 BASE - PCB at bottom"
sketch "V2 cable tie anchor sketch" plane through (0, 0, 3) normal (0, 0, 1) x (1, 0, 0) in component "01 BASE - PCB at bottom"
  line L0 (37, 169) -> (44, 169)
  line L1 (44, 169) -> (44, 174)
  line L2 (44, 174) -> (37, 174)
  line L3 (37, 174) -> (37, 169)
extrude "V2 cable tie anchor" add sketch "V2 cable tie anchor sketch" along normal blind 8 bodies 1 in component "01 BASE - PCB at bottom"
ref_plane "WorkPlane20" through (0, 0, 5) normal (0, 0, 1) x (1, 0, 0) in component "01 BASE - PCB at bottom"
sketch "V2 cable tie tunnel sketch" plane through (0, 0, 5) normal (0, 0, 1) x (1, 0, 0) in component "01 BASE - PCB at bottom"
  line L0 (38.5, 168.9) -> (42.5, 168.9)
  line L1 (42.5, 168.9) -> (42.5, 174.1)
  line L2 (42.5, 174.1) -> (38.5, 174.1)
  line L3 (38.5, 174.1) -> (38.5, 168.9)
extrude "V2 cable tie tunnel" cut sketch "V2 cable tie tunnel sketch" along normal blind 3 bodies 1 in component "01 BASE - PCB at bottom"
ref_plane "WorkPlane21" through (0, 0, 3) normal (0, 0, 1) x (1, 0, 0) in component "01 BASE - PCB at bottom"
sketch "V2 cable tie anchor sketch (1)" plane through (0, 0, 3) normal (0, 0, 1) x (1, 0, 0) in component "01 BASE - PCB at bottom"
  line L0 (99, 169) -> (106, 169)
  line L1 (106, 169) -> (106, 174)
  line L2 (106, 174) -> (99, 174)
  line L3 (99, 174) -> (99, 169)
extrude "V2 cable tie anchor (1)" add sketch "V2 cable tie anchor sketch (1)" along normal blind 8 bodies 1 in component "01 BASE - PCB at bottom"
ref_plane "WorkPlane22" through (0, 0, 5) normal (0, 0, 1) x (1, 0, 0) in component "01 BASE - PCB at bottom"
sketch "V2 cable tie tunnel sketch (1)" plane through (0, 0, 5) normal (0, 0, 1) x (1, 0, 0) in component "01 BASE - PCB at bottom"
  line L0 (100.5, 168.9) -> (104.5, 168.9)
  line L1 (104.5, 168.9) -> (104.5, 174.1)
  line L2 (104.5, 174.1) -> (100.5, 174.1)
  line L3 (100.5, 174.1) -> (100.5, 168.9)
extrude "V2 cable tie tunnel (1)" cut sketch "V2 cable tie tunnel sketch (1)" along normal blind 3 bodies 1 in component "01 BASE - PCB at bottom"
ref_plane "WorkPlane17" through (0, 0, 52) normal (0, 0, 1) x (1, 0, 0) in component "02 LID - LCD buttons LEDs"
sketch "V2 refill old lid and extend sketch" plane through (0, 0, 52) normal (0, 0, 1) x (1, 0, 0) in component "02 LID - LCD buttons LEDs"
  line L0 (6, 0) -> (134, 0)
  line L1 (140, 6) -> (140, 174)
  line L2 (134, 180) -> (6, 180)
  line L3 (0, 174) -> (0, 6)
  arc A0 (134, 0) -> (140, 6) centre (134, 6) ccw
  arc A1 (140, 174) -> (134, 180) centre (134, 174) ccw
  arc A2 (6, 180) -> (0, 174) centre (6, 174) ccw
  arc A3 (0, 6) -> (6, 0) centre (6, 6) ccw
extrude "V2 refill old lid and extend" add sketch "V2 refill old lid and extend sketch" along normal blind 15 bodies 2 in component "02 LID - LCD buttons LEDs"
ref_plane "WorkPlane18" through (0, 0, 39) normal (0, 0, 1) x (1, 0, 0) in component "02 LID - LCD buttons LEDs"
sketch "V2 remove obsolete underside spacers sketch" plane through (0, 0, 39) normal (0, 0, 1) x (1, 0, 0) in component "02 LID - LCD buttons LEDs"
  line L0 (-1, -1) -> (141, -1)
  line L1 (141, -1) -> (141, 181)
  line L2 (141, 181) -> (-1, 181)
  line L3 (-1, 181) -> (-1, -1)
extrude "V2 remove obsolete underside spacers" cut sketch "V2 remove obsolete underside spacers sketch" along normal blind 25 bodies 2 in component "02 LID - LCD buttons LEDs"
ref_plane "WorkPlane19" through (0, 0, 60) normal (0, 0, 1) x (1, 0, 0) in component "02 LID - LCD buttons LEDs"
sketch "V2 lip segments" plane through (0, 0, 60) normal (0, 0, 1) x (1, 0, 0) in component "02 LID - LCD buttons LEDs"
  line L0 (3.3, 16) -> (5.3, 16)
  line L1 (5.3, 16) -> (5.3, 164)
  line L2 (5.3, 164) -> (3.3, 164)
  line L3 (3.3, 164) -> (3.3, 16)
  line L4 (134.7, 16) -> (136.7, 16)
  line L5 (136.7, 16) -> (136.7, 164)
  line L6 (136.7, 164) -> (134.7, 164)
  line L7 (134.7, 164) -> (134.7, 16)
  line L8 (16, 3.3) -> (124, 3.3)
  line L9 (124, 3.3) -> (124, 5.3)
  line L10 (124, 5.3) -> (16, 5.3)
  line L11 (16, 5.3) -> (16, 3.3)
  line L12 (16, 174.7) -> (124, 174.7)
  line L13 (124, 174.7) -> (124, 176.7)
  line L14 (124, 176.7) -> (16, 176.7)
  line L15 (16, 176.7) -> (16, 174.7)
extrude "V2 alignment lips" add sketch "V2 lip segments" along normal blind 4 bodies 2 in component "02 LID - LCD buttons LEDs"
ref_plane "WorkPlane20" through (0, 0, 63.9) normal (0, 0, 1) x (1, 0, 0) in component "02 LID - LCD buttons LEDs"
sketch "V2 cover clearance sketch" plane through (0, 0, 63.9) normal (0, 0, 1) x (1, 0, 0) in component "02 LID - LCD buttons LEDs"
  circle A0 centre (8, 8) radius 1.7
  circle A1 centre (132, 8) radius 1.7
  circle A2 centre (8, 172) radius 1.7
  circle A3 centre (132, 172) radius 1.7
extrude "V2 cover clearance" cut sketch "V2 cover clearance sketch" along normal blind 3.2 bodies 2 in component "02 LID - LCD buttons LEDs"
ref_plane "WorkPlane21" through (0, 0, 65.8) normal (0, 0, 1) x (1, 0, 0) in component "02 LID - LCD buttons LEDs"
sketch "V2 cover head recess sketch" plane through (0, 0, 65.8) normal (0, 0, 1) x (1, 0, 0) in component "02 LID - LCD buttons LEDs"
  circle A0 centre (8, 8) radius 3.2
  circle A1 centre (132, 8) radius 3.2
  circle A2 centre (8, 172) radius 3.2
  circle A3 centre (132, 172) radius 3.2
extrude "V2 cover head recess" cut sketch "V2 cover head recess sketch" along normal blind 1.3 bodies 2 in component "02 LID - LCD buttons LEDs"
ref_plane "WorkPlane22" through (0, 0, 63.9) normal (0, 0, 1) x (1, 0, 0) in component "02 LID - LCD buttons LEDs"
sketch "V2 LCD aperture sketch" plane through (0, 0, 63.9) normal (0, 0, 1) x (1, 0, 0) in component "02 LID - LCD buttons LEDs"
  line L0 (30.5, 114.5) -> (109.5, 114.5)
  line L1 (109.5, 114.5) -> (109.5, 141.5)
  line L2 (109.5, 141.5) -> (30.5, 141.5)
  line L3 (30.5, 141.5) -> (30.5, 114.5)
extrude "V2 LCD aperture" cut sketch "V2 LCD aperture sketch" along normal blind 3.3 bodies 2 in component "02 LID - LCD buttons LEDs"
ref_plane "WorkPlane23" through (0, 0, 54) normal (0, 0, 1) x (1, 0, 0) in component "02 LID - LCD buttons LEDs"
sketch "V2 LCD pillars sketch" plane through (0, 0, 54) normal (0, 0, 1) x (1, 0, 0) in component "02 LID - LCD buttons LEDs"
  circle A0 centre (23.5, 100.5) radius 3.5
  circle A1 centre (116.5, 100.5) radius 3.5
  circle A2 centre (23.5, 155.5) radius 3.5
  circle A3 centre (116.5, 155.5) radius 3.5
extrude "V2 LCD pillars" add sketch "V2 LCD pillars sketch" along normal blind 10 bodies 2 in component "02 LID - LCD buttons LEDs"
ref_plane "WorkPlane24" through (0, 0, 53.9) normal (0, 0, 1) x (1, 0, 0) in component "02 LID - LCD buttons LEDs"
sketch "V2 LCD pilot holes sketch" plane through (0, 0, 53.9) normal (0, 0, 1) x (1, 0, 0) in component "02 LID - LCD buttons LEDs"
  circle A0 centre (23.5, 100.5) radius 1.25
  circle A1 centre (116.5, 100.5) radius 1.25
  circle A2 centre (23.5, 155.5) radius 1.25
  circle A3 centre (116.5, 155.5) radius 1.25
extrude "V2 LCD pilot holes" cut sketch "V2 LCD pilot holes sketch" along normal blind 8.1 bodies 2 in component "02 LID - LCD buttons LEDs"
ref_plane "WorkPlane25" through (0, 0, 63.9) normal (0, 0, 1) x (1, 0, 0) in component "02 LID - LCD buttons LEDs"
sketch "V2 control module opening sketch" plane through (0, 0, 63.9) normal (0, 0, 1) x (1, 0, 0) in component "02 LID - LCD buttons LEDs"
  line L0 (51, 27) -> (89, 27)
  line L1 (92, 30) -> (92, 64)
  line L2 (89, 67) -> (51, 67)
  line L3 (48, 64) -> (48, 30)
  arc A0 (89, 27) -> (92, 30) centre (89, 30) ccw
  arc A1 (92, 64) -> (89, 67) centre (89, 64) ccw
  arc A2 (51, 67) -> (48, 64) centre (51, 64) ccw
  arc A3 (48, 30) -> (51, 27) centre (51, 30) ccw
extrude "V2 control module opening" cut sketch "V2 control module opening sketch" along normal blind 3.3 bodies 2 in component "02 LID - LCD buttons LEDs"
ref_plane "WorkPlane26" through (0, 0, 58) normal (0, 0, 1) x (1, 0, 0) in component "02 LID - LCD buttons LEDs"
sketch "V2 control fascia screw bosses sketch" plane through (0, 0, 58) normal (0, 0, 1) x (1, 0, 0) in component "02 LID - LCD buttons LEDs"
  circle A0 centre (43, 32) radius 3.5
  circle A1 centre (97, 32) radius 3.5
  circle A2 centre (43, 62) radius 3.5
  circle A3 centre (97, 62) radius 3.5
extrude "V2 control fascia screw bosses" add sketch "V2 control fascia screw bosses sketch" along normal blind 6 bodies 2 in component "02 LID - LCD buttons LEDs"
ref_plane "WorkPlane27" through (0, 0, 58.1) normal (0, 0, 1) x (1, 0, 0) in component "02 LID - LCD buttons LEDs"
sketch "V2 fascia screw pilots sketch" plane through (0, 0, 58.1) normal (0, 0, 1) x (1, 0, 0) in component "02 LID - LCD buttons LEDs"
  circle A0 centre (43, 32) radius 1.25
  circle A1 centre (97, 32) radius 1.25
  circle A2 centre (43, 62) radius 1.25
  circle A3 centre (97, 62) radius 1.25
extrude "V2 fascia screw pilots" cut sketch "V2 fascia screw pilots sketch" along normal blind 9 bodies 2 in component "02 LID - LCD buttons LEDs"
ref_plane "WorkPlane28" through (0, 0, 67) normal (0, 0, 1) x (1, 0, 0) in component "02 LID - LCD buttons LEDs"
sketch "V2 text H2 PRO" plane through (0, 0, 67) normal (0, 0, 1) x (1, 0, 0) in component "02 LID - LCD buttons LEDs"
  line L0 (30, 164) -> (110, 164) construction
  line L1 (110, 164) -> (110, 170) construction
  line L2 (110, 170) -> (30, 170) construction
  line L3 (30, 170) -> (30, 164) construction
  dimension "d407" = 5
  dimension "d408" = 0
  text T0 "H2 PRO" font "Arial" height 5 align centre middle in box 80 x 6 at (30, 164) x (1, 0) y (0, 1) spacing 1 kerned
extrude "V2 engrave H2 PRO" cut sketch "V2 text H2 PRO" against normal blind 0.35 text T0 bodies 2 in component "02 LID - LCD buttons LEDs"
ref_plane "WorkPlane29" through (0, 0, 67) normal (0, 0, 1) x (1, 0, 0) in component "02 LID - LCD buttons LEDs"
sketch "V2 text BRAIN / CONTROL UNIT" plane through (0, 0, 67) normal (0, 0, 1) x (1, 0, 0) in component "02 LID - LCD buttons LEDs"
  line L0 (20, 89) -> (120, 89) construction
  line L1 (120, 89) -> (120, 95) construction
  line L2 (120, 95) -> (20, 95) construction
  line L3 (20, 95) -> (20, 89) construction
  dimension "d413" = 2.8
  text T0 "BRAIN / CONTROL UNIT" font "Arial" height 2.8 align centre middle in box 100 x 6 at (20, 89) x (1, 0) y (0, 1) spacing 1 kerned
extrude "V2 engrave BRAIN / CONTROL UNIT" cut sketch "V2 text BRAIN / CONTROL UNIT" against normal blind 0.35 text T0 bodies 2 in component "02 LID - LCD buttons LEDs"
ref_plane "WorkPlane30" through (0, 0, 67) normal (0, 0, 1) x (1, 0, 0) in component "02 LID - LCD buttons LEDs"
sketch "V2 text POWER   LOCK   PURGE" plane through (0, 0, 67) normal (0, 0, 1) x (1, 0, 0) in component "02 LID - LCD buttons LEDs"
  line L0 (15, 72) -> (125, 72) construction
  line L1 (125, 72) -> (125, 78) construction
  line L2 (125, 78) -> (15, 78) construction
  line L3 (15, 78) -> (15, 72) construction
  dimension "d419" = 3
  text T0 "POWER   LOCK   PURGE" font "Arial" height 3 align centre middle in box 110 x 6 at (15, 72) x (1, 0) y (0, 1) spacing 1 kerned
extrude "V2 engrave POWER   LOCK   PURGE" cut sketch "V2 text POWER   LOCK   PURGE" against normal blind 0.35 text T0 bodies 2 in component "02 LID - LCD buttons LEDs"